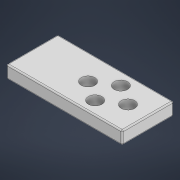
# Autodesk Inventor part: endstop_pad
Saved by Autodesk Inventor 2021 (Build 250183000, 183)
## iProperties
Created: 2022-05-12
Part Number: endstop_pad
Material: Generic
Document SubType Name: Modeling
Designer: DELL
Density: 1 g/cm^3
Appearance: Default
Author: DELL
Autodesk Inventor part; units mm, degrees
ref_plane "YZ Plane" through (0, 0, 0) normal (1, 0, 0) x (0, 1, 0)
ref_plane "XZ Plane" through (0, 0, 0) normal (0, 1, 0) x (-1, 0, 0)
ref_plane "XY Plane" through (0, 0, 0) normal (0, 0, 1) x (1, 0, 0)
sketch "Sketch1" plane through (0, 0, 0) normal (0, 1, 0) x (-1, 0, 0)
  line L0 (45, 0) -> (0, 0)
  line L1 (0, 0) -> (0, -20)
  line L2 (0, -20) -> (45, -20)
  line L3 (45, -20) -> (45, 0)
  line L4 (31, 0) -> (31, -20)
  line L5 (15.5, 0) -> (15.5, -20) construction
  line L6 (31, -10) -> (0, -10) construction
  circle A0 centre (7.75, -10) radius 2.65
  circle A1 centre (23.25, -10) radius 2.65
  circle A2 centre (15.5, -15) radius 2.65
  circle A3 centre (15.5, -5) radius 2.65
  dimension "d0" = 20
  dimension "d1" = 45
  dimension "d2" = 14
  dimension "d3" = 5.3
  dimension "d4" = 7.75
  dimension "d5" = 5.3
  dimension "d6" = 5
  constraints: 14 end point, 6 point on line, 4 centre point, 2 midpoint, 2 parallel, 2 perpendicular, 2 symmetric about line, 1 coincident, 1 horizontal, 1 vertical, 3 other
  measures "d0" distance of L0.end L1.end
  measures "d1" distance of L0.start L0.end
  measures "d2" distance between parallel lines of L3 L4
  measures "d3" diameter of A0
  measures "d4" distance from line of L1 A0.centre
  measures "d5" diameter of A2
  measures "d6" distance from line of L6 A2.centre
extrude "Extrusion1" add sketch "Sketch1" along normal blind 5
fillet "Fillet1" radius 0.5 12 edges at (-22.5, 5, 0) (-22.5, 0, 0) (-22.5, 5, -20) (-22.5, 0, -20) (0, 5, -10) (0, 0, -10) (0, 2.5, 0) (0, 2.5, -20) (-45, 2.5, 0) (-45, 2.5, -20) (-45, 0, -10) (-45, 5, -10)
equation "\"d4\" = -0.25 * d2 + 0.25 * d1"
body "Solid1"
